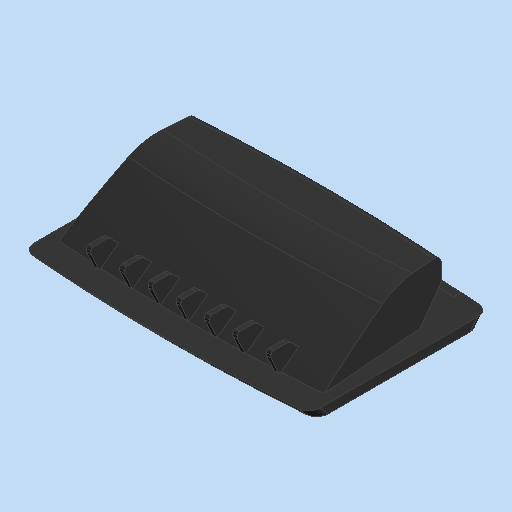
# Autodesk Inventor part: MM0861AN115_G02_104
Saved by Autodesk Inventor 2023.3 (Build 273359000, 359)
## iProperties
Part Number: MM0861AN115_G02_104
Material: Generisch
Catalog Web Link: www.cadenas.de
Description: =<RBPARTNOTITLE2>
Vendor: Ganter
Document SubType Name: Modeling
Designer: partserver
Manufacturer: GANTER
Mass: 43 g
Surface Area: 267.88 cm^2
Volume: 33.1236 cm^3
Density: 1 g/cm^3
Appearance: PSOLRGB-63-63-63
Category: PARTsolutions
Company: GANTER
PSOL_IDENT_0: {$CADENAS_DATA\23d-libs\ganter\data\1_2\gn_733\gn_733_o.prj},200 {VTYP=3D},{NB=Gripping tray GN 733-
PSOL_IDENT_1: 110-O-DSG},{LINA=Gripping tray GN 733-110-O-DSG},{NN=GN 733},{DATE=27.04.2020 15:19:35},{GEOMDATE=21
PSOL_IDENT_2: .04.2020 12:47:59},{VERSION=},{LINEID=10},{WBVAR=},{WBNUMERIC=}  {NB=Griffschale GN 733-110-O-DSG},{
PSOL_IDENT_3: LINA=Griffschale GN 733-110-O-DSG},{KT=DUMMY},{PARTNUMBER=GN 733-110-O-DSG},{NORMNR=GN 733},{B1=110}
PSOL_IDENT_4: ,{FARBEVIS=schwarzgrau (DSG)},{B2=90},{B3=96},{H1=73},{H2=42},{L1=24.0},{L2=20},{L3=21.5},{M1=64},{F
PSOL_IDENT_5: ARBEX=DSG},{F1=1300},{F2=500},{COLOR=0.25,0.25,0.25,0.00},{R=0.25},{G=0.25},{B=0.25},{FARBE=1},{WEIG
PSOL_IDENT_6: HT=0.0430},{CTN=39263000},{ROHS=YES},{INFOGANTER=Produktdetails},{INFOGANTERX=https://www.ganternorm
PSOL_IDENT_7: .com/de/produkte/1.2-Bedienen-mit-Maschinen-und-Geraetegriffen/GN-733-Griffschalen-zum-Anschrauben-K
PSOL_IDENT_8: unststoff},{DIST=5.228571},{DIM01=109.000},{DIM03=73.000},{DIM09=42.000},{DIM05=20.000},{DIM10=9.000
PSOL_IDENT_9: }
NB: Gripping tray GN 733-110-O-DSG
NN: GN 733
NT: Gripping trays, Type O without closing flap
NBSYN: Gripping tray $PARTNUMBER.
LINA: Gripping tray GN 733-110-O-DSG
CATALOG: Ganter
PARTNUMBER: GN 733-110-O-DSG
B1: 110
FARBEVIS: black-gray (DSG)
B2: 90
B3: 96
H1: 73
H2: 42
L1: 24
L2: 20
L3: 21.5
M1: 64
F1: 1300
F2: 500
WEIGHT: 0.043
CTN: 39263000
ROHS: YES
INFOGANTER: Product details
SUPPLIER: GANTER
ARTICLENO: Gripping tray GN 733-110-O-DSG
BOMINFO: Gripping tray GN 733-110-O-DSG
CREATOR: CADENAS GmbH
RBSURFACE: --
RBPARTNOTITLE1: Gripping tray
AnP_Kategorie: 2
AnP_Material: =<Material>
RBDRAWINGMISSINGSPEC: --
RBPARTMADEOF: GN 733-110-O-DSG
RBPARTNOTITLE2: Griffschale
RBMATERIAL: --
RBSURFACE2: --
RBMATNO: =<Part Number>
Title: Gripping tray GN 733-110-O-DSG
Author: Cadenas PARTsolutions
Comments: =<RBSURFACE2>
Keywords: =<RBPARTMADEOF>
Revision Number: 01
Autodesk Inventor part; units mm, degrees
ref_plane "YZ Plane" through (0, 0, 0) normal (1, 0, 0) x (0, 1, 0)
ref_plane "XZ Plane" through (0, 0, 0) normal (0, 1, 0) x (-1, 0, 0)
ref_plane "XY Plane" through (0, 0, 0) normal (0, 0, 1) x (1, 0, 0)
sketch "Sketch_26" plane through (0, 0, 0) normal (1, 0, 0) x (0, 1, 0)
  line L0 (-609.9, -20.4) -> (-609.9, -15.101911)
  arc A0 (20.42, -2.5) -> (14.891871, -4.427223) centre (17.32, -2.5) ccw
  line L1 (14.891871, -4.427223) -> (22.786535, -14.373798)
  arc A1 (23.22, -15.617168) -> (22.786535, -14.373798) centre (21.22, -15.617168) ccw
  line L2 (23.22, -15.617168) -> (23.22, -18.9)
  arc A2 (21.22, -20.9) -> (23.22, -18.9) centre (21.22, -18.9) ccw
  line L3 (21.22, -20.9) -> (-14.28, -20.9)
  line L4 (-14.28, -20.9) -> (-14.28, -23.4)
  line L5 (-14.28, -23.4) -> (22.72, -23.4)
  arc A3 (22.72, -23.4) -> (25.72, -20.4) centre (22.72, -20.4) ccw
  line L6 (25.72, -20.4) -> (25.72, -15.101911)
  arc A4 (25.72, -15.101911) -> (25.018133, -13.173548) centre (22.72, -15.101911) ccw
  line L7 (25.018133, -13.173548) -> (16.061963, -2.5)
  line L8 (16.061963, -2.5) -> (20.42, -2.5)
  constraints: 18 end point, 10 point on circle, 5 centre point
revolve "Revolution1" add sketch "Sketch_26" angle 20 mid plane about axis through (0, -609.9, -20.4) along (0, 0, 1)
sketch "Sketch_27" plane through (0, 0, 0) normal (1, 0, 0) x (0, 1, 0)
  line L0 (617.72, -15.101911) -> (617.72, -18.9)
  line L1 (-27.78, 0) -> (-31.28, 0)
  arc A0 (-31.28, 0) -> (-2.149234, -19.971424) centre (156.591739, 242.802821) ccw
  arc A1 (-2.149234, -19.971424) -> (10.157069, -23.4) centre (10.157069, 0.4) ccw
  line L2 (10.157069, -23.4) -> (10.04578, -20.9)
  arc A2 (-2.404566, -17.383709) -> (10.04578, -20.9) centre (10.04578, 2.9) ccw
  arc A3 (-27.78, 0) -> (-2.404566, -17.383709) centre (158.194444, 244.259097) ccw
  constraints: 8 point on circle, 6 end point, 4 centre point
revolve "Revolution2" add sketch "Sketch_27" angle 20 mid plane about axis through (0, 617.72, -15.101911) along (0, 0, -1)
sketch "Sketch_28" plane through (0, 0, 0) normal (0, 0, 1) x (1, 0, 0)
  line L0 (-150, -80) -> (150, -80)
  line L1 (150, -80) -> (150, 70)
  line L2 (150, 70) -> (-150, 70)
  line L3 (-150, 70) -> (-150, -80)
  line L4 (-48.892186, -37.5) -> (48.892186, -37.5)
  line L5 (48.892186, -37.5) -> (42.10232, 50)
  line L6 (42.10232, 50) -> (-42.10232, 50)
  line L7 (-42.10232, 50) -> (-48.892186, -37.5)
  constraints: 16 end point
extrude "Extrusion1" cut sketch "Sketch_28" along normal mid plane 100
sketch "Sketch_29" plane through (0, 0, 0) normal (0, 0, 1) x (1, 0, 0)
  line L0 (42.10232, 50) -> (48.892186, -37.5)
  line L1 (48.892186, -37.5) -> (51.384693, -37.306585)
  line L2 (51.384693, -37.306585) -> (44.594827, 50.193415)
  line L3 (44.594827, 50.193415) -> (42.10232, 50)
  constraints: 8 end point
extrude "Extrusion2" add sketch "Sketch_29" against normal blind 30
sketch "Sketch_30" plane through (0, 0, 0) normal (0, 0, 1) x (1, 0, 0)
  line L0 (-51.384693, -37.306585) -> (-48.892186, -37.5)
  line L1 (-48.892186, -37.5) -> (-42.10232, 50)
  line L2 (-42.10232, 50) -> (-44.594827, 50.193415)
  line L3 (-44.594827, 50.193415) -> (-51.384693, -37.306585)
  constraints: 8 end point
extrude "Extrusion3" add sketch "Sketch_30" against normal blind 30
sketch "Sketch_31" plane through (0, 0, 0) normal (1, 0, 0) x (0, 1, 0)
  line L0 (612.5, 50) -> (612.5, -50)
  line L1 (-50, 15.715055) -> (-50, -40)
  line L2 (-50, -40) -> (30.078535, -40)
  line L3 (30.078535, -40) -> (30.078535, -23.4)
  line L4 (30.078535, -23.4) -> (10.157069, -23.4)
  arc A0 (-2.149234, -19.971424) -> (10.157069, -23.4) centre (10.157069, 0.4) ccw
  arc A1 (-50, 15.715055) -> (-2.149234, -19.971424) centre (156.591739, 242.802821) ccw
  constraints: 10 end point, 4 point on circle, 2 centre point
revolve "Revolution3" cut sketch "Sketch_31" angle 30 mid plane about axis through (0, 612.5, 50) along (0, 0, -1)
sketch "Sketch_32" plane through (0, 0, 0) normal (1, 0, 0) x (0, 1, 0)
  line L0 (-609.9, -20.4) -> (-609.9, -15.101911)
  line L1 (17.32, 10) -> (17.32, 0.6)
  arc A0 (20.42, -2.5) -> (17.32, 0.6) centre (17.32, -2.5) ccw
  line L2 (20.42, -2.5) -> (16.061963, -2.5)
  line L3 (16.061963, -2.5) -> (25.018133, -13.173548)
  arc A1 (25.72, -15.101911) -> (25.018133, -13.173548) centre (22.72, -15.101911) ccw
  line L4 (25.72, -15.101911) -> (25.72, -20.4)
  arc A2 (22.72, -23.4) -> (25.72, -20.4) centre (22.72, -20.4) ccw
  line L5 (22.72, -23.4) -> (-14.28, -23.4)
  line L6 (-14.28, -23.4) -> (-14.28, -30)
  line L7 (-14.28, -30) -> (100, -30)
  line L8 (100, -30) -> (100, 10)
  line L9 (100, 10) -> (17.32, 10)
  constraints: 20 end point, 6 point on circle, 3 centre point
revolve "Revolution4" cut sketch "Sketch_32" angle 40 mid plane about axis through (0, -609.9, -20.4) along (0, 0, 1)
sketch "Sketch_1" plane through (0, 0, 0) normal (0, 0, 1) x (1, 0, 0)
  line L0 (0, -33.35) -> (0, -27.78)
  arc A0 (-48, -26.002527) -> (0, -27.78) centre (0, 621.22) ccw
  line L1 (-48, -26.002527) -> (-45, 14.662838)
  arc A1 (0, 16.22) -> (-45, 14.662838) centre (0, -634.78) ccw
  line L2 (0, 16.22) -> (0, 19.22)
  arc A2 (0, 19.22) -> (-44.777022, 17.685339) centre (0, -634.78) ccw
  line L3 (-44.777022, 17.685339) -> (-43.730207, 31.875033)
  arc A3 (-43.730207, 31.875033) -> (-50.44198, 31.386789) centre (0, -615.65) ccw
  arc A4 (-50.44198, 31.386789) -> (-54.5, 27.000099) centre (-50.1, 27.000099) ccw
  line L4 (-54.5, 27.000099) -> (-54.5, -27.000099)
  arc A5 (-54.5, -27.000099) -> (-50.441979, -31.386789) centre (-50.1, -27.000099) ccw
  arc A6 (-50.441979, -31.386789) -> (0, -33.35) centre (0, 615.65) ccw
  constraints: 14 point on circle, 10 end point, 7 centre point
sketch "Sketch_2" plane through (0, 0, -3.5) normal (0, 0, 1) x (1, 0, 0)
  line L0 (0, -36.5) -> (0, -23.78)
  arc A0 (-48, -21.991474) -> (0, -23.78) centre (0, 621.22) ccw
  line L1 (-48, -21.991474) -> (-45, 13.660437)
  arc A1 (0, 15.22) -> (-45, 13.660437) centre (0, -634.78) ccw
  line L2 (0, 15.22) -> (0, 19.22)
  arc A2 (0, 19.22) -> (-44.660646, 17.693315) centre (0, -634.78) ccw
  line L3 (-44.660646, 17.693315) -> (-43.207697, 34.960109)
  arc A3 (-43.207697, 34.960109) -> (-50.44198, 34.436789) centre (0, -612.6) ccw
  arc A4 (-50.44198, 34.436789) -> (-54.5, 30.050099) centre (-50.1, 30.050099) ccw
  line L4 (-54.5, 30.050099) -> (-54.5, -30.150099)
  arc A5 (-54.5, -30.150099) -> (-50.441979, -34.536789) centre (-50.1, -30.150099) ccw
  arc A6 (-50.441979, -34.536789) -> (0, -36.5) centre (0, 612.5) ccw
  constraints: 14 point on circle, 10 end point, 7 centre point
loft "Loft1" add profiles "Sketch_2", "Sketch_1"
sketch "Sketch_19" plane through (0, 0, -3.5) normal (0, 0, 1) x (1, 0, 0)
  arc A0 (0, -36.5) -> (50.44198, -34.536789) centre (0, 612.5) ccw
  arc A1 (50.44198, -34.536789) -> (54.5, -30.150099) centre (50.1, -30.150099) ccw
  line L0 (54.5, -30.150099) -> (54.5, 30.050099)
  arc A2 (54.5, 30.050099) -> (50.44198, 34.436789) centre (50.1, 30.050099) ccw
  arc A3 (50.44198, 34.436789) -> (43.207697, 34.960109) centre (0, -612.6) ccw
  line L1 (43.207697, 34.960109) -> (44.660646, 17.693315)
  arc A4 (44.660646, 17.693315) -> (0, 19.22) centre (0, -634.78) ccw
  line L2 (0, 19.22) -> (0, 15.22)
  arc A5 (45, 13.660437) -> (0, 15.22) centre (0, -634.78) ccw
  line L3 (45, 13.660437) -> (48, -21.991474)
  arc A6 (0, -23.78) -> (48, -21.991474) centre (0, 621.22) ccw
  line L4 (0, -23.78) -> (0, -36.5)
  constraints: 14 point on circle, 10 end point, 7 centre point
sketch "Sketch_20" plane through (0, 0, 0) normal (0, 0, 1) x (1, 0, 0)
  arc A0 (0, -33.35) -> (50.44198, -31.386789) centre (0, 615.65) ccw
  arc A1 (50.44198, -31.386789) -> (54.5, -27.000099) centre (50.1, -27.000099) ccw
  line L0 (54.5, -27.000099) -> (54.5, 27.000099)
  arc A2 (54.5, 27.000099) -> (50.441979, 31.386789) centre (50.1, 27.000099) ccw
  arc A3 (50.441979, 31.386789) -> (43.730207, 31.875033) centre (0, -615.65) ccw
  line L1 (43.730207, 31.875033) -> (44.777022, 17.685339)
  arc A4 (44.777022, 17.685339) -> (0, 19.22) centre (0, -634.78) ccw
  line L2 (0, 19.22) -> (0, 16.22)
  arc A5 (45, 14.662838) -> (0, 16.22) centre (0, -634.78) ccw
  line L3 (45, 14.662838) -> (48, -26.002527)
  arc A6 (0, -27.78) -> (48, -26.002527) centre (0, 621.22) ccw
  line L4 (0, -27.78) -> (0, -33.35)
  constraints: 14 point on circle, 10 end point, 7 centre point
loft "Loft2" add profiles "Sketch_19", "Sketch_20"
sketch "Sketch_22" plane through (0, 0, -0.2) normal (0, 0, 1) x (1, 0, 0)
  arc A0 (44.777022, 17.685339) -> (-44.777022, 17.685339) centre (0, -634.78) ccw
  line L0 (44.777022, 17.685339) -> (43.730207, 31.875033)
  arc A1 (43.730207, 31.875033) -> (-43.730207, 31.875033) centre (0, -615.65) ccw
  line L1 (-43.730207, 31.875033) -> (-44.777022, 17.685339)
  constraints: 4 end point, 4 point on circle, 2 centre point
sketch "Sketch_33" plane through (0, 0, -3.5) normal (0, 0, 1) x (1, 0, 0)
  arc A0 (44.660646, 17.693315) -> (-44.660646, 17.693315) centre (0, -634.78) ccw
  line L0 (44.660646, 17.693315) -> (43.453679, 32.036871)
  arc A1 (43.453679, 32.036871) -> (-43.453679, 32.036871) centre (0, -612.5) ccw
  line L1 (-43.453679, 32.036871) -> (-44.660646, 17.693315)
  constraints: 4 end point, 4 point on circle, 2 centre point
loft "Loft3" add profiles "Sketch_33", "Sketch_22"
sketch "Sketch_10" plane through (29.25, 0, 0) normal (1, 0, 0) x (0, 0, -1)
  line L0 (2.5, 13.960432) -> (3.100238, 13.689313)
  line L1 (3.100238, 13.689313) -> (13.667128, 23)
  line L2 (13.667128, 23) -> (8.69438, 23)
  arc A0 (8.69438, 23) -> (8.319774, 22.927184) centre (8.69438, 22) ccw
  line L3 (8.319774, 22.927184) -> (2.5, 20.575843)
  line L4 (2.5, 20.575843) -> (2.5, 13.960432)
  constraints: 10 end point, 2 point on circle, 1 centre point
extrude "Extrusion4" add sketch "Sketch_10" along normal mid plane 1.3
sketch "Sketch_3" plane through (19.5, 0, 0) normal (1, 0, 0) x (0, 0, -1)
  line L0 (3, 15.600992) -> (4.500594, 14.923193)
  line L1 (4.500594, 14.923193) -> (13.667128, 23)
  line L2 (13.667128, 23) -> (8.69438, 23)
  arc A0 (8.69438, 23) -> (8.319774, 22.927184) centre (8.69438, 22) ccw
  line L3 (8.319774, 22.927184) -> (3, 20.777856)
  line L4 (3, 20.777856) -> (3, 15.600992)
  constraints: 10 end point, 2 point on circle, 1 centre point
extrude "Extrusion5" add sketch "Sketch_3" along normal mid plane 1.3
sketch "Sketch_4" plane through (9.75, 0, 0) normal (1, 0, 0) x (0, 0, -1)
  line L0 (3, 16.600992) -> (5.250891, 15.584294)
  line L1 (5.250891, 15.584294) -> (13.667128, 23)
  line L2 (13.667128, 23) -> (8.69438, 23)
  arc A0 (8.69438, 23) -> (8.319774, 22.927184) centre (8.69438, 22) ccw
  line L3 (8.319774, 22.927184) -> (3, 20.777856)
  line L4 (3, 20.777856) -> (3, 16.600992)
  constraints: 10 end point, 2 point on circle, 1 centre point
extrude "Extrusion6" add sketch "Sketch_4" along normal mid plane 1.3
sketch "Sketch_5" plane through (0, 0, 0) normal (1, 0, 0) x (0, 0, -1)
  line L0 (3, 16.382698) -> (4.551581, 15.644679)
  line L1 (4.551581, 15.644679) -> (13.594806, 23)
  line L2 (13.594806, 23) -> (8.69438, 23)
  arc A0 (8.69438, 23) -> (8.319774, 22.927184) centre (8.69438, 22) ccw
  line L3 (8.319774, 22.927184) -> (3, 20.777856)
  line L4 (3, 20.777856) -> (3, 16.382698)
  constraints: 10 end point, 2 point on circle, 1 centre point
extrude "Extrusion7" add sketch "Sketch_5" along normal mid plane 1.3
sketch "Sketch_23" plane through (-9.75, 0, 0) normal (1, 0, 0) x (0, 0, -1)
  line L0 (3, 16.600992) -> (5.250891, 15.584294)
  line L1 (5.250891, 15.584294) -> (13.667128, 23)
  line L2 (13.667128, 23) -> (8.69438, 23)
  arc A0 (8.69438, 23) -> (8.319774, 22.927184) centre (8.69438, 22) ccw
  line L3 (8.319774, 22.927184) -> (3, 20.777856)
  line L4 (3, 20.777856) -> (3, 16.600992)
  constraints: 10 end point, 2 point on circle, 1 centre point
extrude "Extrusion8" add sketch "Sketch_23" along normal mid plane 1.3
sketch "Sketch_6" plane through (-19.5, 0, 0) normal (1, 0, 0) x (0, 0, -1)
  line L0 (3, 15.600992) -> (4.500594, 14.923193)
  line L1 (4.500594, 14.923193) -> (13.667128, 23)
  line L2 (13.667128, 23) -> (8.69438, 23)
  arc A0 (8.69438, 23) -> (8.319774, 22.927184) centre (8.69438, 22) ccw
  line L3 (8.319774, 22.927184) -> (3, 20.777856)
  line L4 (3, 20.777856) -> (3, 15.600992)
  constraints: 10 end point, 2 point on circle, 1 centre point
extrude "Extrusion9" add sketch "Sketch_6" along normal mid plane 1.3
sketch "Sketch_24" plane through (-29.25, 0, 0) normal (1, 0, 0) x (0, 0, -1)
  line L0 (2.5, 13.960432) -> (3.100238, 13.689313)
  line L1 (3.100238, 13.689313) -> (13.667128, 23)
  line L2 (13.667128, 23) -> (8.69438, 23)
  arc A0 (8.69438, 23) -> (8.319774, 22.927184) centre (8.69438, 22) ccw
  line L3 (8.319774, 22.927184) -> (2.5, 20.575843)
  line L4 (2.5, 20.575843) -> (2.5, 13.960432)
  constraints: 10 end point, 2 point on circle, 1 centre point
extrude "Extrusion10" add sketch "Sketch_24" along normal mid plane 1.3
sketch "Sketch_11" plane through (0, 0, 0) normal (1, 0, 0) x (0, 1, 0)
  line L0 (-26.275846, -3) -> (-29.54, -10)
  line L1 (-29.54, -10) -> (-29.54, -11)
  arc A0 (-29.54, -11) -> (-28.54, -12) centre (-28.54, -11) ccw
  line L2 (-28.54, -12) -> (-23.782641, -12)
  arc A1 (-23.782641, -12) -> (-21.66132, -11.12132) centre (-23.782641, -9) ccw
  line L3 (-21.66132, -11.12132) -> (-18.201643, -7.661643)
  line L4 (-18.201643, -7.661643) -> (-26.275846, -3)
  constraints: 10 end point, 4 point on circle, 2 centre point
extrude "Extrusion11" add sketch "Sketch_11" along normal mid plane 1.75
sketch "Sketch_25" plane through (10.77, 0, 0) normal (1, 0, 0) x (0, 0, -1)
  line L0 (3, -26.275846) -> (10, -29.54)
  line L1 (10, -29.54) -> (11, -29.54)
  arc A0 (11, -29.54) -> (12, -28.54) centre (11, -28.54) ccw
  line L2 (12, -28.54) -> (12, -23.782641)
  arc A1 (12, -23.782641) -> (11.12132, -21.66132) centre (9, -23.782641) ccw
  line L3 (11.12132, -21.66132) -> (7.661643, -18.201643)
  line L4 (7.661643, -18.201643) -> (3, -26.275846)
  constraints: 10 end point, 4 point on circle, 2 centre point
extrude "Extrusion12" add sketch "Sketch_25" along normal mid plane 1.75
sketch "Sketch_8" plane through (21.54, 0, 0) normal (1, 0, 0) x (0, 0, -1)
  line L0 (3, -24.24712) -> (3, -26.275846)
  line L1 (3, -26.275846) -> (10, -29.54)
  line L2 (10, -29.54) -> (11, -29.54)
  arc A0 (11, -29.54) -> (12, -28.54) centre (11, -28.54) ccw
  line L3 (12, -28.54) -> (12, -23.782641)
  arc A1 (12, -23.782641) -> (11.12132, -21.66132) centre (9, -23.782641) ccw
  line L4 (11.12132, -21.66132) -> (7.178388, -17.718388)
  line L5 (7.178388, -17.718388) -> (3, -24.24712)
  constraints: 12 end point, 4 point on circle, 2 centre point
extrude "Extrusion13" add sketch "Sketch_8" along normal mid plane 1.75
sketch "Sketch_9" plane through (34.31, 0, 0) normal (1, 0, 0) x (0, 0, -1)
  line L0 (3, -24.24712) -> (3, -26.275846)
  line L1 (3, -26.275846) -> (10, -29.54)
  line L2 (10, -29.54) -> (11, -29.54)
  arc A0 (11, -29.54) -> (12, -28.54) centre (11, -28.54) ccw
  line L3 (12, -28.54) -> (12, -23.782641)
  arc A1 (12, -23.782641) -> (11.12132, -21.66132) centre (9, -23.782641) ccw
  line L4 (11.12132, -21.66132) -> (7.178388, -17.718388)
  line L5 (7.178388, -17.718388) -> (3, -24.24712)
  constraints: 12 end point, 4 point on circle, 2 centre point
extrude "Extrusion14" add sketch "Sketch_9" along normal mid plane 1.75
sketch "Sketch_12" plane through (-10.77, 0, 0) normal (1, 0, 0) x (0, 0, -1)
  line L0 (3, -26.275846) -> (10, -29.54)
  line L1 (10, -29.54) -> (11, -29.54)
  arc A0 (11, -29.54) -> (12, -28.54) centre (11, -28.54) ccw
  line L2 (12, -28.54) -> (12, -23.782641)
  arc A1 (12, -23.782641) -> (11.12132, -21.66132) centre (9, -23.782641) ccw
  line L3 (11.12132, -21.66132) -> (7.661643, -18.201643)
  line L4 (7.661643, -18.201643) -> (3, -26.275846)
  constraints: 10 end point, 4 point on circle, 2 centre point
extrude "Extrusion15" add sketch "Sketch_12" along normal mid plane 1.75
sketch "Sketch_13" plane through (-21.54, 0, 0) normal (1, 0, 0) x (0, 0, -1)
  line L0 (3, -24.24712) -> (3, -26.275846)
  line L1 (3, -26.275846) -> (10, -29.54)
  line L2 (10, -29.54) -> (11, -29.54)
  arc A0 (11, -29.54) -> (12, -28.54) centre (11, -28.54) ccw
  line L3 (12, -28.54) -> (12, -23.782641)
  arc A1 (12, -23.782641) -> (11.12132, -21.66132) centre (9, -23.782641) ccw
  line L4 (11.12132, -21.66132) -> (7.178388, -17.718388)
  line L5 (7.178388, -17.718388) -> (3, -24.24712)
  constraints: 12 end point, 4 point on circle, 2 centre point
extrude "Extrusion16" add sketch "Sketch_13" along normal mid plane 1.75
sketch "Sketch_21" plane through (-34.31, 0, 0) normal (1, 0, 0) x (0, 0, -1)
  line L0 (3, -23.690589) -> (3, -26.275846)
  line L1 (3, -26.275846) -> (10, -29.54)
  line L2 (10, -29.54) -> (11, -29.54)
  arc A0 (11, -29.54) -> (12, -28.54) centre (11, -28.54) ccw
  line L3 (12, -28.54) -> (12, -23.782641)
  arc A1 (12, -23.782641) -> (11.12132, -21.66132) centre (9, -23.782641) ccw
  line L4 (11.12132, -21.66132) -> (6.961205, -17.501205)
  line L5 (6.961205, -17.501205) -> (3, -23.690589)
  constraints: 12 end point, 4 point on circle, 2 centre point
extrude "Extrusion17" add sketch "Sketch_21" along normal mid plane 1.75
sketch "Sketch_15" plane through (0, 0, 0) normal (0, 0, 1) x (1, 0, 0)
  arc A0 (44.298469, 18.419614) -> (-44.298469, 18.419614) centre (0, -634.78) ccw
  line L0 (44.298469, 18.419614) -> (42.896481, 35.0808)
  arc A1 (42.896481, 35.0808) -> (-42.896481, 35.0808) centre (0, -612.5) ccw
  line L1 (-42.896481, 35.0808) -> (-44.298469, 18.419614)
  constraints: 4 end point, 4 point on circle, 2 centre point
extrude "Extrusion18" add sketch "Sketch_15" against normal blind 3.4
sketch "Sketch_16" plane through (0, 0, 0) normal (1, 0, 0) x (0, 0, -1)
  line L0 (50, -612.5) -> (-50, -612.5)
  line L1 (-5, 29.214286) -> (7.583333, 40)
  line L2 (7.583333, 40) -> (-5, 40)
  line L3 (-5, 40) -> (-5, 29.214286)
  constraints: 8 end point
revolve "Revolution5" cut sketch "Sketch_16" angle 8 mid plane about axis through (0, -612.5, -50) along (0, 0, 1)
sketch "Sketch_17" plane through (0, 0, 0.2) normal (0, 0, 1) x (1, 0, 0)
  circle A0 centre (-10, 26.13) radius 1.4
  constraints: 1 centre point
extrude "Extrusion19" add sketch "Sketch_17" against normal blind 1
pattern_linear "Rectangular Pattern1" count 5 spacing 5 along (1, 0, 0) of "Extrusion19"
sketch "Sketch31" plane through (-54.5, -30.150099, -3.5) normal (0, 0, -1) x (-1, 0, 0)
  point P0 (-22.5, 58.650099)
hole "Hole1" at (-32, 28.5, -3.5) direction (0, 0, 1) diameter 2.6 depth 2.2
sketch "Sketch32" plane through (-54.5, -30.150099, -3.5) normal (0, 0, -1) x (-1, 0, 0)
  point P0 (-86.5, 58.650099)
hole "Hole2" at (32, 28.5, -3.5) direction (0, 0, 1) diameter 2.6 depth 2.2
body "Solid1"
